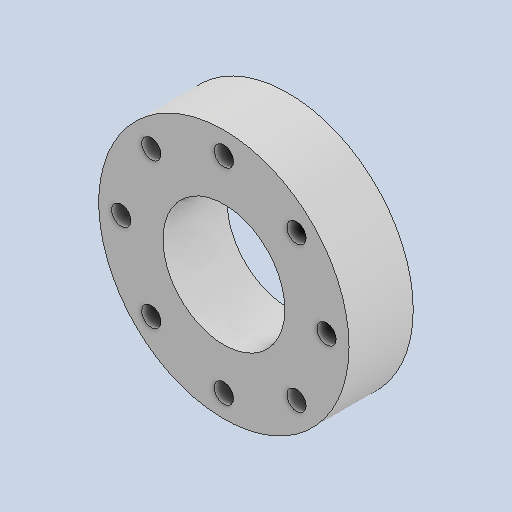
# Autodesk Inventor part: ConnectorBodytoArm
Saved by Autodesk Inventor 2025.2 (Build 292293000, 293)
## iProperties
Created: 2025-06-27
Part Number: ConnectorBodytoArm
Material: Generic
Document SubType Name: Modeling
Designer: ricoa
Density: 1 g/cm^3
Appearance: Default
Author: ricoa
Autodesk Inventor part; units mm, degrees
ref_plane "YZ Plane" through (0, 0, 0) normal (1, 0, 0) x (0, 1, 0)
ref_plane "XZ Plane" through (0, 0, 0) normal (0, 1, 0) x (-1, 0, 0)
ref_plane "XY Plane" through (0, 0, 0) normal (0, 0, 1) x (1, 0, 0)
sketch "Sketch1" plane through (0, 0, 0) normal (0, 0, 1) x (1, 0, 0)
  circle A0 centre (0, 0) radius 9.75 projected
  circle A1 centre (0, 0) radius 4 projected
  circle A2 centre (-5.6569, 5.6569) radius 0.75 projected
  circle A3 centre (-8, 0) radius 0.75 projected
  circle A4 centre (-5.6569, -5.6569) radius 0.75 projected
  circle A5 centre (0, -8) radius 0.75 projected
  circle A6 centre (5.6569, -5.6569) radius 0.75 projected
  circle A7 centre (8, 0) radius 0.75 projected
  circle A8 centre (5.6569, 5.6569) radius 0.75 projected
  circle A9 centre (0, 8) radius 0.75 projected
  circle A10 centre (0, 0) radius 4.75 projected
  point P0 (0, 0)
extrude "Extrusion1" add sketch "Sketch1" along normal blind 5 contours A0
body "Solid1"
